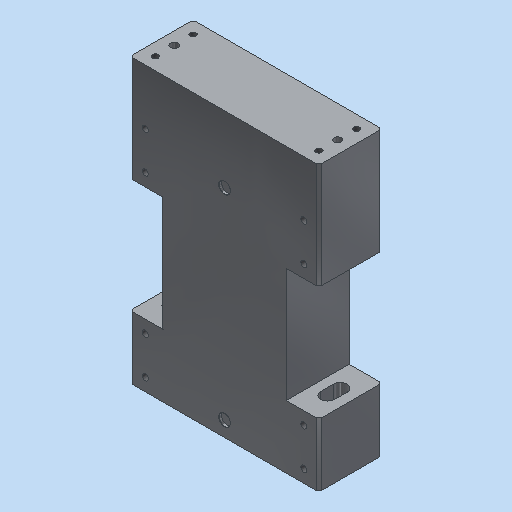
# Autodesk Inventor part: MM0868AN100_G80_101
Saved by Autodesk Inventor 2023.3 (Build 273359000, 359)
## iProperties
RuleStatus: InUse
Created: 2020-12-03
Part Number: MM0868AN100_G80_101
Material: 3.3547 AlMg4,5Mn0,7 - AW 5083
Description: =<RBPARTNOTITLE2>
Document SubType Name: Modeling
Designer: RUD
Mass: 3845.4 g
Surface Area: 1084.71 cm^2
Volume: 1424.22 cm^3
Density: 2.7 g/cm^3
Appearance: Aluminium AnP
AnP_Kategorie: 1
AnP_Material: =<Material>
AnP_TemplVers: 20200821
RBDOCUMENTTYPE: DRF
RBDOCUMENTVERSION: 00
RBDRAWINGMAINSCALE: 1:1
RBDRAWINGMISSINGSPEC: --
RBDRAWINGVOLUME: --
RBDSV1: 0850
RBGBEDGESIN1: +0,5
RBGBEDGESIN2: +0,2
RBGBEDGESOUT1: -0,3
RBGBEDGESOUT2: -0,1
RBMATERIAL: =<Material>
RBMATMEETS: --
RBMATNO: =<Part Number>
RBPARTMADEOF: Fl.150x50x228
RBPARTNO: SIEHE MNR
RBPARTNOTITLE1: manufactured part
RBPARTNOTITLE2: Anfertigungsteil
RBPARTSAFETYINDICATOR: --
RBSURFACE: anodised colourless
RBSURFACE2: eloxiert farblos
RBZEDGESNORM: ISO13715:2002-06
RBZGENDIMCLASS: m
RBZGENDIMNORM: ISO 2768-1:1989-11
RBZGENGEOCLASS: H
RBZGENGEONORM: ISO 2768-2:1989-11
RBZSURFACENORM: ISO13D2:2002-02
RBZTOLERANCENORM: ISO 14405-1:2010-12
Author: RUD
Keywords: =<RBPARTMADEOF>
Comments: =<RBSURFACE2>
Revision Number: 01
Autodesk Inventor part; units mm, degrees
ref_plane "YZ Plane" through (0, 0, 0) normal (1, 0, 0) x (0, 1, 0)
ref_plane "XZ Plane" through (0, 0, 0) normal (0, 1, 0) x (-1, 0, 0)
ref_plane "XY Plane" through (0, 0, 0) normal (0, 0, 1) x (1, 0, 0)
sketch "Skizze1" plane through (0, 0, 0) normal (0, 0, 1) x (1, 0, 0)
  line L0 (0, 270) -> (0, -45) projected
  line L1 (-109.534, 0) -> (132.2038, 0) projected
  line L2 (-75, 0) -> (75, 0)
  line L3 (75, 0) -> (75, 225)
  line L4 (75, 225) -> (-75, 225)
  line L5 (-75, 225) -> (-75, 0)
  dimension "d0" = 150
  dimension "d1" = 225
  constraints: 8 end point, 2 parallel, 1 collinear, 1 horizontal, 1 perpendicular, 1 other
  measures "d0" distance between parallel lines of L3 L5
  measures "d1" distance between parallel lines of L2 L4
extrude "Extrusion1" add sketch "Skizze1" against normal mid plane 50
sketch "Skizze2" plane through (0, 0, 25) normal (0, 0, 1) x (1, 0, 0)
  line L0 (-75, 0) -> (75, 0) projected
  line L1 (-75, 225) -> (-75, 0) projected
  line L2 (75, 0) -> (75, 225) projected
  line L3 (-75, 141) -> (-49, 141)
  line L4 (-49, 141) -> (-49, 50)
  line L5 (-49, 50) -> (-76.5712, 50)
  line L6 (75, 141) -> (49, 141)
  line L7 (49, 141) -> (49, 50)
  line L8 (49, 50) -> (75, 50)
  line L9 (0, 270) -> (0, -45) projected
  point P0 (-75, 50)
  dimension "d6" = 50
  dimension "d7" = 91
  dimension "d8" = 26
  constraints: 12 end point, 4 perpendicular, 3 point on line, 2 collinear, 2 horizontal, 1 other
  measures "d6" distance between parallel lines of L0 L5
  measures "d7" distance between parallel lines of L5 L3
  measures "d8" distance between parallel lines of L1 L4
extrude "Extrusion2" cut sketch "Skizze2" against normal through all
sketch "Skizze3" plane through (-75, 50, 25) normal (0, 1, 0) x (1, 0, 0)
  line L0 (13, 30) -> (13, 20) construction
  line L1 (18.5, 30) -> (18.5, 20)
  line L2 (7.5, 20) -> (7.5, 30)
  arc A0 (18.5, 30) -> (7.5, 30) centre (13, 30) ccw
  arc A1 (7.5, 20) -> (18.5, 20) centre (13, 20) ccw
  line L3 (137, 30) -> (137, 20) construction
  line L4 (131.5, 30) -> (131.5, 20)
  line L5 (142.5, 20) -> (142.5, 30)
  arc A2 (142.5, 30) -> (131.5, 30) centre (137, 30) ccw
  arc A3 (131.5, 20) -> (142.5, 20) centre (137, 20) ccw
  line L6 (75, 60) -> (75, -10) projected
  line L7 (180, 25) -> (-30, 25) projected
  line L8 (26, 0) -> (0, 0) projected
  point P0 (13, 25)
  point P1 (137, 25)
  point P2 (13, 0)
  dimension "d11" = 11
  dimension "d12" = 10
  constraints: 16 end point, 8 point on circle, 8 tangent, 4 centre point, 4 parallel, 3 midpoint, 2 point on line, 1 equal radius, 1 symmetric about line, 1 vertical
  measures "d11" distance between parallel lines of L2 L1
  measures "d12" distance of L2.start L2.end
extrude "Extrusion3" cut sketch "Skizze3" against normal through all
sketch "Skizze4" plane through (0, 0, 25) normal (0, 0, 1) x (1, 0, 0)
  line L0 (0, 270) -> (0, -45) projected
  line L1 (-105, 0) -> (105, 0) projected
  line L2 (-63, 10) -> (-63, 40)
  point P0 (63, 10)
  point P1 (63, 40)
  dimension "d31" = 126
  dimension "d32" = 10
  dimension "d36" = 30
  constraints: 2 end point, 2 symmetric about line, 1 coincident, 1 vertical
  measures "d31" distance of point (63, 10) L2.start
  measures "d32" distance from line of L1 L2.start
  measures "d36" distance of L2.start L2.end
hole "Bohrung1" at (-63, 10, 25) at (63, 10, 25) at (-63, 40, 25) at (63, 40, 25) direction (0, 0, -1) diameter 4.917 depth 20 tip angle 118 thread size "M6x1" designation "M6" class "6H" standard "ISO Metric profile"
pattern_linear "Rechteckige Anordnung1" count 2 spacing 141 along (0, 1, 0) of "Bohrung1"
sketch "Skizze5" plane through (0, 0, 25) normal (0, 0, 1) x (1, 0, 0)
  line L0 (0, 270) -> (0, -45) projected
  line L1 (-105, 0) -> (105, 0) projected
  point P0 (0, 172)
  point P1 (0, 12)
  dimension "d22" = 12
  dimension "d23" = 160
  constraints: 2 point on line
  measures "d22" distance from line of L1 point (0, 12)
  measures "d23" distance of point (0, 12) point (0, 172)
hole "Bohrung2" at (0, 172, 25) at (0, 12, 25) direction (0, 0, -1) diameter 9 depth 2.1
sketch "Skizze6" plane through (-75, 225, -25) normal (0, 1, 0) x (1, 0, 0)
  line L0 (75, 10) -> (75, -60) projected
  line L1 (180, -25) -> (-30, -25) projected
  point P0 (140, -10)
  point P1 (140, -40)
  point P2 (10, -40)
  point P3 (10, -10)
  dimension "d37" = 30
  dimension "d38" = 130
  constraints: 3 symmetric about line
  measures "d37" distance of point (140, -10) point (140, -40)
  measures "d38" distance of point (10, -10) point (140, -10)
hole "Bohrung3" at (65, 225, -15) at (65, 225, 15) at (-65, 225, 15) at (-65, 225, -15) direction (0, -1, 0) diameter 4.917 depth 20 tip angle 118 thread size "M6x1" designation "M6" class "6H" standard "ISO Metric profile"
sketch "Skizze7" plane through (-75, 225, -25) normal (0, 1, 0) x (1, 0, 0)
  circle A0 centre (140, -10) radius 2.4585 projected
  circle A1 centre (140, -40) radius 2.4585 projected
  line L0 (75, 10) -> (75, -60) projected
  line L1 (140, -10) -> (140, -40)
  point P0 (140, -25)
  point P1 (10, -25)
  constraints: 2 end point, 1 midpoint, 1 symmetric about line, 1 vertical
hole "Bohrung4" at (65, 225, 0) at (-65, 225, 0) direction (0, -1, 0) diameter 6 depth 10 tip angle 118
chamfer "Fase1" distance 2 angle 45 8 edges at (-75, 183, 25) (-75, 183, -25) (75, 183, -25) (75, 183, 25) (75, 25, -25) (75, 25, 25) (-75, 25, -25) (-75, 25, 25)
chamfer "Fase2" distance 0.2 angle 45 2 edges at (0, 176.5, 25) (0, 16.5, 25)
